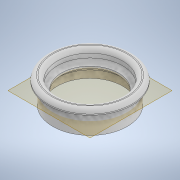
# Autodesk Inventor part: suport_binoclu
Saved by Autodesk Inventor 2022.6 (Build 266554000, 554)
## iProperties
Created: 2025-11-23
Part Number: suport_binoclu
Material: Generic
Document SubType Name: Modeling
Designer: Dragos Macovei
Density: 1 g/cm^3
Appearance: Default
Author: Dragos Macovei
Autodesk Inventor part; units mm, degrees
ref_plane "YZ Plane" through (0, 0, 0) normal (1, 0, 0) x (0, 1, 0)
ref_plane "XZ Plane" through (0, 0, 0) normal (0, 1, 0) x (-1, 0, 0)
ref_plane "XY Plane" through (0, 0, 0) normal (0, 0, 1) x (1, 0, 0)
sketch "Sketch1" plane through (0, 0, 0) normal (0, 1, 0) x (-1, 0, 0)
  circle A0 centre (0, 0) radius 36
  circle A1 centre (0, 0) radius 31.5
  dimension "d0" = 72
  dimension "d1" = 63
  constraints: 2 centre point, 2 coincident
  measures "d0" diameter of A0
  measures "d1" diameter of A1
extrude "Extrusion1" add sketch "Sketch1" along normal blind 20
ref_plane "Work Plane1" through (0, 12, 0) normal (0, 1, 0) x (1, 0, 0)
sketch "Sketch2" plane through (0, 12, 0) normal (0, 1, 0) x (1, 0, 0)
  circle A0 centre (0, 0) radius 31.5 projected
  circle A1 centre (0, 0) radius 27.5
  dimension "d5" = 55
  constraints: 1 centre point, 1 coincident
  measures "d5" diameter of A1
extrude "Extrusion2" add sketch "Sketch2" along normal mid plane 2
fillet "Fillet1" radius 4 1 edges at (31.5, 13, 0)
fillet "Fillet2" radius 4 1 edges at (31.5, 11, 0)
sketch "Sketch3" plane through (0, 0, 0) normal (1, 0, 0) x (0, 1, 0)
  line L0 (20, -36) -> (20, 36) projected
  line L1 (0, -36) -> (0, 36) projected
  line L2 (20, 31.5) -> (20, -31.5) projected
  line L3 (20, -31.5) -> (21, -31.5)
  line L4 (25, -35.5) -> (25, -36.5)
  line L5 (21, -40.5) -> (20, -40.5)
  line L6 (20, -36) -> (20, 36) projected
  line L7 (20, -40.5) -> (20, -36)
  arc A0 (25, -35.5) -> (21, -31.5) centre (21, -35.5) ccw
  arc A1 (21, -40.5) -> (25, -36.5) centre (21, -36.5) ccw
  line L8 (-5.1657, 0) -> (30.9941, 0) projected
  point P0 (0, 0)
  point P1 (25, -31.5)
  point P2 (25, -40.5)
  dimension "d10" = 5
  dimension "d11" = 9
  dimension "d12" = 4
  constraints: 8 end point, 4 point on circle, 4 point on line, 4 tangent, 2 centre point, 2 perpendicular, 1 equal radius, 1 horizontal, 1 vertical
  measures "d10" distance of L2.end point (25, -31.5)
  measures "d11" distance of point (25, -31.5) point (25, -40.5)
  measures "d12" radius of A0
revolve "Revolution1" add sketch "Sketch3" angle 360 about axis through (0, -10, 0) along (0, 1, 0)
body "Solid1"
